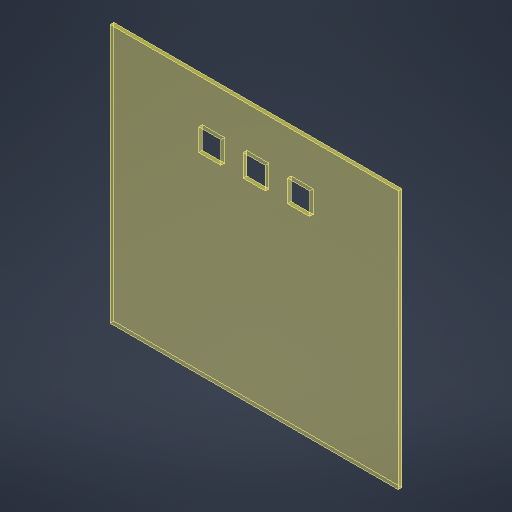
# Autodesk Inventor part: Glass
Saved by Autodesk Inventor 2027 (Build 310192060, 192F)
## iProperties
Created: 2026-10-17
Part Number: Glass
Material: Générique
Document SubType Name: Modeling
Designer: strei
Density: 1 g/cm^3
Appearance: Transparent - Jaune
Author: strei
Autodesk Inventor part; units mm, degrees
ref_plane "YZ Plane" through (0, 0, 0) normal (1, 0, 0) x (0, 1, 0)
ref_plane "XZ Plane" through (0, 0, 0) normal (0, 1, 0) x (-1, 0, 0)
ref_plane "XY Plane" through (0, 0, 0) normal (0, 0, 1) x (1, 0, 0)
sketch "Esquisse1" plane through (0, 0, 0) normal (0, 0, 1) x (1, 0, 0)
  line L0 (-390, 350) -> (390, 350)
  line L1 (390, 350) -> (390, -350)
  line L2 (390, -350) -> (-390, -350)
  line L3 (-390, -350) -> (-390, 350)
  line L4 (-390, 350) -> (390, -350) construction
  line L5 (390, 350) -> (-390, -350) construction
  line L6 (-30, 230) -> (30, 230)
  line L7 (30, 230) -> (30, 170)
  line L8 (30, 170) -> (-30, 170)
  line L9 (-30, 170) -> (-30, 230)
  line L10 (-30, 230) -> (30, 170) construction
  line L11 (30, 230) -> (-30, 170) construction
  line L12 (-390, 200) -> (390, 200) construction
  line L13 (90, 230) -> (150, 230)
  line L14 (150, 230) -> (150, 170)
  line L15 (150, 170) -> (90, 170)
  line L16 (90, 170) -> (90, 230)
  line L17 (90, 230) -> (150, 170) construction
  line L18 (150, 230) -> (90, 170) construction
  line L19 (-150, 230) -> (-90, 230)
  line L20 (-90, 230) -> (-90, 170)
  line L21 (-90, 170) -> (-150, 170)
  line L22 (-150, 170) -> (-150, 230)
  line L23 (-150, 230) -> (-90, 170) construction
  line L24 (-90, 230) -> (-150, 170) construction
  line L25 (-30, 230) -> (30, 230)
  line L26 (30, 230) -> (30, 170)
  line L27 (30, 170) -> (-30, 170)
  line L28 (-30, 170) -> (-30, 230)
  line L29 (-30, 230) -> (30, 170) construction
  line L30 (30, 230) -> (-30, 170) construction
  point P0 (0, 0)
  point P1 (0, 200)
  point P2 (120, 200)
  point P3 (-120, 200)
  point P4 (0, 200)
  dimension "d0" = 780
  dimension "d1" = 700
  dimension "d2" = 60
  dimension "d3" = 60
  dimension "d4" = 200
  dimension "d7" = 120
  dimension "d10" = 120
  constraints: 62 end point, 5 midpoint, 4 horizontal, 4 parallel, 3 perpendicular, 2 point on line, 1 vertical alignment, 33 other
  measures "d0" distance of L1.end L2.end
  measures "d1" distance of L0.end L1.end
  measures "d2" distance of L7.end L8.end
  measures "d3" distance of L6.end L7.end
  measures "d4" distance from line of point (0, 0) L12
  measures "d7" distance of L6.start L13.start
  measures "d10" distance of L6.start L19.start
extrude "Extrusion1" add sketch "Esquisse1" along normal mid plane 10
equation "\"d10\" = d7"
